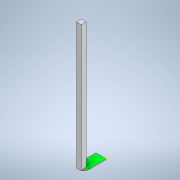
# Autodesk Inventor part: suport_balustrada
Saved by Autodesk Inventor 2022.6 (Build 266554000, 554)
## iProperties
Created: 2026-11-01
Part Number: suport_balustrada
Material: Generic
Document SubType Name: Modeling
Designer: Dragos Macovei
Density: 1 g/cm^3
Appearance: Default
Author: Dragos Macovei
Autodesk Inventor part; units mm, degrees
ref_plane "YZ Plane" through (0, 0, 0) normal (1, 0, 0) x (0, 1, 0)
ref_plane "XZ Plane" through (0, 0, 0) normal (0, 1, 0) x (-1, 0, 0)
ref_plane "XY Plane" through (0, 0, 0) normal (0, 0, 1) x (1, 0, 0)
sketch "Sketch1" plane through (0, 0, 0) normal (0, 1, 0) x (-1, 0, 0)
  line L0 (0, 0) -> (50, 0)
  line L1 (50, 0) -> (50, 80)
  line L2 (50, 80) -> (0, 80)
  line L3 (0, 80) -> (0, 0)
  line L4 (37, 108) -> (13, 108) construction
  line L5 (13, 108) -> (13, 84) construction
  line L6 (13, 84) -> (37, 84) construction
  line L7 (37, 84) -> (37, 108) construction
  arc A0 (50, 80) -> (37, 108) centre (13.3462, 80) ccw
  arc A1 (13, 108) -> (0, 80) centre (36.6538, 80) ccw
  line L8 (37, 108) -> (13, 108)
  point P0 (25, 84)
  point P1 (25, 108)
  dimension "d0" = 50
  dimension "d1" = 80
  dimension "d13" = 24
  dimension "d14" = 24
  dimension "d15" = 4
  dimension "d17" = 25
  dimension "d18" = 13
  dimension "d19" = 13
  constraints: 18 end point, 4 parallel, 4 point on circle, 2 centre point, 2 horizontal, 2 midpoint, 2 perpendicular, 2 tangent
  measures "d0" distance of L2.end L1.end
  measures "d1" distance of L1.end L0.end
  measures "d13" distance of L6.end L5.end
  measures "d14" distance of L5.end L4.end
  measures "d15" distance from line of L2 point (25, 84)
  measures "d17" distance from line of L3 point (25, 108)
  measures "d18" distance between parallel lines of L3 L5
  measures "d19" distance between parallel lines of L1 L7
extrude "Extrusion1" add sketch "Sketch1" along normal blind 4
sketch "Sketch5" plane through (0, 4, 0) normal (0, 1, 0) x (1, 0, 0)
  point P0 (0, 0)
sketch "Sketch6" plane through (0, 4, 0) normal (0, 1, 0) x (1, 0, 0)
  line L0 (-50, 0) -> (-50, -80) projected
  arc A0 (-50, -80) -> (-37, -108) centre (-13.3462, -80) ccw projected
  line L1 (-37, -108) -> (-13, -108) projected
  arc A1 (-13, -108) -> (0, -80) centre (-36.6538, -80) ccw projected
  line L2 (0, -80) -> (0, 0) projected
  line L3 (0, 0) -> (-50, 0) projected
  line L4 (-37, -108) -> (-13, -108) projected
  line L5 (-37, -108) -> (-13, -108)
  line L6 (-13, -108) -> (-13, -84)
  line L7 (-13, -84) -> (-37, -84)
  line L8 (-37, -84) -> (-37, -108)
  dimension "d20" = 24
  dimension "d21" = 24
  constraints: 8 end point, 2 parallel, 1 horizontal, 1 perpendicular
  measures "d20" distance of L7.end L6.end
  measures "d21" distance of L6.end L5.end
extrude "Extrusion5" add sketch "Sketch6" along normal blind 610 contours L8 L7 L6 L1
body "Solid1"
